Autodesk Fusion 360 part; units mm, degrees
(part 5 of 7)
ref_plane "WorkPlane1" through (-328.5, 0, 0) normal (1, 0, 0) x (0, 1, 0) in component "rear right rail mount 2-1 M6 cap screw"
sketch "New stock profile (83)" plane through (-328.5, 0, 0) normal (1, 0, 0) x (0, 0, -1) in component "rear right rail mount 2-1 M6 cap screw"
  circle A0 centre (-84.1, -195.15) radius 3
extrude "New 1''''''''''''''''''''''''''''''''''''''''''''''''''''''''''''''''''''''''''''''''''" add sketch "New stock profile (83)" along normal blind 40 separate body makes body 209 in component "rear right rail mount 2-1 M6 cap screw"
ref_plane "WorkPlane2" through (-288.5, 0, 0) normal (1, 0, 0) x (0, 1, 0) in component "rear right rail mount 2-1 M6 cap screw"
sketch "Join stock profile (29)" plane through (-288.5, 0, 0) normal (1, 0, 0) x (0, 0, -1) in component "rear right rail mount 2-1 M6 cap screw"
  circle A0 centre (-84.1, -195.15) radius 5
extrude "Join 2''''''''''''''''''''''''''''" add sketch "Join stock profile (29)" along normal blind 6 bodies 209 in component "rear right rail mount 2-1 M6 cap screw"
ref_plane "WorkPlane3" through (-282.49, 0, 0) normal (1, 0, 0) x (0, 1, 0) in component "rear right rail mount 2-1 M6 cap screw"
sketch "Cut stock profile (53)" plane through (-282.49, 0, 0) normal (1, 0, 0) x (0, 0, -1) in component "rear right rail mount 2-1 M6 cap screw"
  line L0 (-84.1, -198.0368) -> (-86.6, -196.5934)
  line L1 (-86.6, -196.5934) -> (-86.6, -193.7066)
  line L2 (-86.6, -193.7066) -> (-84.1, -192.2632)
  line L3 (-84.1, -192.2632) -> (-81.6, -193.7066)
  line L4 (-81.6, -193.7066) -> (-81.6, -196.5934)
  line L5 (-81.6, -196.5934) -> (-84.1, -198.0368)
extrude "Cut 3''''''''''''''''''''''''''''''''''''" cut sketch "Cut stock profile (53)" against normal blind 3.01 bodies 209 in component "rear right rail mount 2-1 M6 cap screw"
ref_plane "WorkPlane1" through (-330.6, 0, 0) normal (1, 0, 0) x (0, 1, 0) in component "rear right rail mount 2-2 weld boss"
sketch "New stock profile (84)" plane through (-330.6, 0, 0) normal (1, 0, 0) x (0, 0, -1) in component "rear right rail mount 2-2 weld boss"
  circle A0 centre (-105.1, -195.15) radius 6.5
  circle A1 centre (-105.1, -195.15) radius 2.5
extrude "New 1'''''''''''''''''''''''''''''''''''''''''''''''''''''''''''''''''''''''''''''''''''" add sketch "New stock profile (84)" along normal blind 16 separate body makes body 210 in component "rear right rail mount 2-2 weld boss"
ref_plane "WorkPlane1" through (-328.5, 0, 0) normal (1, 0, 0) x (0, 1, 0) in component "rear right rail mount 2-2 M6 cap screw"
sketch "New stock profile (85)" plane through (-328.5, 0, 0) normal (1, 0, 0) x (0, 0, -1) in component "rear right rail mount 2-2 M6 cap screw"
  circle A0 centre (-105.1, -195.15) radius 3
extrude "New 1''''''''''''''''''''''''''''''''''''''''''''''''''''''''''''''''''''''''''''''''''''" add sketch "New stock profile (85)" along normal blind 40 separate body makes body 211 in component "rear right rail mount 2-2 M6 cap screw"
ref_plane "WorkPlane2" through (-288.5, 0, 0) normal (1, 0, 0) x (0, 1, 0) in component "rear right rail mount 2-2 M6 cap screw"
sketch "Join stock profile (30)" plane through (-288.5, 0, 0) normal (1, 0, 0) x (0, 0, -1) in component "rear right rail mount 2-2 M6 cap screw"
  circle A0 centre (-105.1, -195.15) radius 5
extrude "Join 2'''''''''''''''''''''''''''''" add sketch "Join stock profile (30)" along normal blind 6 bodies 211 in component "rear right rail mount 2-2 M6 cap screw"
ref_plane "WorkPlane3" through (-282.49, 0, 0) normal (1, 0, 0) x (0, 1, 0) in component "rear right rail mount 2-2 M6 cap screw"
sketch "Cut stock profile (54)" plane through (-282.49, 0, 0) normal (1, 0, 0) x (0, 0, -1) in component "rear right rail mount 2-2 M6 cap screw"
  line L0 (-105.1, -198.0368) -> (-107.6, -196.5934)
  line L1 (-107.6, -196.5934) -> (-107.6, -193.7066)
  line L2 (-107.6, -193.7066) -> (-105.1, -192.2632)
  line L3 (-105.1, -192.2632) -> (-102.6, -193.7066)
  line L4 (-102.6, -193.7066) -> (-102.6, -196.5934)
  line L5 (-102.6, -196.5934) -> (-105.1, -198.0368)
extrude "Cut 3'''''''''''''''''''''''''''''''''''''" cut sketch "Cut stock profile (54)" against normal blind 3.01 bodies 211 in component "rear right rail mount 2-2 M6 cap screw"
ref_plane "WorkPlane1" through (0, 0, 65.5637) normal (0, 0, 1) x (1, 0, 0) in component "rear right tab 2-1 socket screw"
sketch "New stock profile (86)" plane through (0, 0, 65.5637) normal (0, 0, 1) x (1, 0, 0) in component "rear right tab 2-1 socket screw"
  circle A0 centre (-296.75, -207.85) radius 2.413
extrude "New 1'''''''''''''''''''''''''''''''''''''''''''''''''''''''''''''''''''''''''''''''''''''" add sketch "New stock profile (86)" along normal blind 69.85 separate body makes body 212 in component "rear right tab 2-1 socket screw"
ref_plane "WorkPlane2" through (0, 0, 60.7378) normal (0, 0, 1) x (1, 0, 0) in component "rear right tab 2-1 socket screw"
sketch "Join stock profile (31)" plane through (0, 0, 60.7378) normal (0, 0, 1) x (1, 0, 0) in component "rear right tab 2-1 socket screw"
  circle A0 centre (-296.75, -207.85) radius 3.9624
extrude "Join 2''''''''''''''''''''''''''''''" add sketch "Join stock profile (31)" along normal blind 4.826 bodies 212 in component "rear right tab 2-1 socket screw"
ref_plane "WorkPlane3" through (0, 0, 60.7278) normal (0, 0, 1) x (1, 0, 0) in component "rear right tab 2-1 socket screw"
sketch "Cut stock profile (55)" plane through (0, 0, 60.7278) normal (0, 0, 1) x (1, 0, 0) in component "rear right tab 2-1 socket screw"
  line L0 (-294.4586, -207.85) -> (-295.6043, -205.8656)
  line L1 (-295.6043, -205.8656) -> (-297.8957, -205.8656)
  line L2 (-297.8957, -205.8656) -> (-299.0414, -207.85)
  line L3 (-299.0414, -207.85) -> (-297.8957, -209.8344)
  line L4 (-297.8957, -209.8344) -> (-295.6043, -209.8344)
  line L5 (-295.6043, -209.8344) -> (-294.4586, -207.85)
extrude "Cut 3''''''''''''''''''''''''''''''''''''''" cut sketch "Cut stock profile (55)" along normal blind 2.296 bodies 212 in component "rear right tab 2-1 socket screw"
ref_plane "WorkPlane1" through (0, 0, 124.3125) normal (0, 0, 1) x (1, 0, 0) in component "rear right tab 2-1 locknut"
sketch "New stock profile (87)" plane through (0, 0, 124.3125) normal (0, 0, 1) x (1, 0, 0) in component "rear right tab 2-1 locknut"
  line L0 (-291.2361, -207.85) -> (-293.993, -203.0748)
  line L1 (-293.993, -203.0748) -> (-299.507, -203.0748)
  line L2 (-299.507, -203.0748) -> (-302.2639, -207.85)
  line L3 (-302.2639, -207.85) -> (-299.507, -212.6252)
  line L4 (-299.507, -212.6252) -> (-293.993, -212.6252)
  line L5 (-293.993, -212.6252) -> (-291.2361, -207.85)
  circle A0 centre (-296.75, -207.85) radius 2.43
extrude "New 1''''''''''''''''''''''''''''''''''''''''''''''''''''''''''''''''''''''''''''''''''''''" add sketch "New stock profile (87)" along normal blind 6.3246 separate body makes body 213 in component "rear right tab 2-1 locknut"
ref_plane "WorkPlane1" through (0, 0, 65.5637) normal (0, 0, 1) x (1, 0, 0) in component "rear right tab 2-2 socket screw"
sketch "New stock profile (88)" plane through (0, 0, 65.5637) normal (0, 0, 1) x (1, 0, 0) in component "rear right tab 2-2 socket screw"
  circle A0 centre (-296.75, -182.45) radius 2.413
extrude "New 1'''''''''''''''''''''''''''''''''''''''''''''''''''''''''''''''''''''''''''''''''''''''" add sketch "New stock profile (88)" along normal blind 69.85 separate body makes body 214 in component "rear right tab 2-2 socket screw"
ref_plane "WorkPlane2" through (0, 0, 60.7378) normal (0, 0, 1) x (1, 0, 0) in component "rear right tab 2-2 socket screw"
sketch "Join stock profile (32)" plane through (0, 0, 60.7378) normal (0, 0, 1) x (1, 0, 0) in component "rear right tab 2-2 socket screw"
  circle A0 centre (-296.75, -182.45) radius 3.9624
extrude "Join 2'''''''''''''''''''''''''''''''" add sketch "Join stock profile (32)" along normal blind 4.826 bodies 214 in component "rear right tab 2-2 socket screw"
ref_plane "WorkPlane3" through (0, 0, 60.7278) normal (0, 0, 1) x (1, 0, 0) in component "rear right tab 2-2 socket screw"
sketch "Cut stock profile (56)" plane through (0, 0, 60.7278) normal (0, 0, 1) x (1, 0, 0) in component "rear right tab 2-2 socket screw"
  line L0 (-294.4586, -182.45) -> (-295.6043, -180.4656)
  line L1 (-295.6043, -180.4656) -> (-297.8957, -180.4656)
  line L2 (-297.8957, -180.4656) -> (-299.0414, -182.45)
  line L3 (-299.0414, -182.45) -> (-297.8957, -184.4344)
  line L4 (-297.8957, -184.4344) -> (-295.6043, -184.4344)
  line L5 (-295.6043, -184.4344) -> (-294.4586, -182.45)
extrude "Cut 3'''''''''''''''''''''''''''''''''''''''" cut sketch "Cut stock profile (56)" along normal blind 2.296 bodies 214 in component "rear right tab 2-2 socket screw"
ref_plane "WorkPlane1" through (0, 0, 124.3125) normal (0, 0, 1) x (1, 0, 0) in component "rear right tab 2-2 locknut"
sketch "New stock profile (89)" plane through (0, 0, 124.3125) normal (0, 0, 1) x (1, 0, 0) in component "rear right tab 2-2 locknut"
  line L0 (-291.2361, -182.45) -> (-293.993, -177.6748)
  line L1 (-293.993, -177.6748) -> (-299.507, -177.6748)
  line L2 (-299.507, -177.6748) -> (-302.2639, -182.45)
  line L3 (-302.2639, -182.45) -> (-299.507, -187.2252)
  line L4 (-299.507, -187.2252) -> (-293.993, -187.2252)
  line L5 (-293.993, -187.2252) -> (-291.2361, -182.45)
  circle A0 centre (-296.75, -182.45) radius 2.43
extrude "New 1''''''''''''''''''''''''''''''''''''''''''''''''''''''''''''''''''''''''''''''''''''''''" add sketch "New stock profile (89)" along normal blind 6.3246 separate body makes body 215 in component "rear right tab 2-2 locknut"
ref_plane "WorkPlane1" through (0, 0, 3.1) normal (0, 0, 1) x (1, 0, 0) in component "front left public drive housing"
sketch "New stock profile (90)" plane through (0, 0, 3.1) normal (0, 0, 1) x (1, 0, 0) in component "front left public drive housing"
  circle A0 centre (-3, -3) radius 30
  circle A1 centre (-3, -3) radius 20
extrude "New 1'''''''''''''''''''''''''''''''''''''''''''''''''''''''''''''''''''''''''''''''''''''''''" add sketch "New stock profile (90)" along normal blind 48 separate body makes body 216 in component "front left public drive housing"
ref_plane "WorkPlane2" through (0, 0, -1.9) normal (0, 0, 1) x (1, 0, 0) in component "front left public drive housing"
sketch "Join stock profile (33)" plane through (0, 0, -1.9) normal (0, 0, 1) x (1, 0, 0) in component "front left public drive housing"
  line L0 (-29, -29) -> (-15, -29)
  line L1 (-15, -29) -> (-15, -15)
  line L2 (-15, -15) -> (-29, -15)
  line L3 (-29, -15) -> (-29, -29)
extrude "Join 2''''''''''''''''''''''''''''''''" add sketch "Join stock profile (33)" along normal blind 53 bodies 216 in component "front left public drive housing"
ref_plane "WorkPlane3" through (0, 0, -4.4362) normal (0, 0, 1) x (1, 0, 0) in component "front left public drive housing"
sketch "Join stock profile (1)" plane through (0, 0, -4.4362) normal (0, 0, 1) x (1, 0, 0) in component "front left public drive housing"
  line L0 (-29, -28) -> (-22, -28)
  line L1 (-22, -28) -> (-22, 33)
  line L2 (-22, 33) -> (-29, 33)
  line L3 (-29, 33) -> (-29, -28)
extrude "Join 3" add sketch "Join stock profile (1)" along normal blind 4.2863 bodies 216 in component "front left public drive housing"
ref_plane "WorkPlane4" through (0, 0, -4.4362) normal (0, 0, 1) x (1, 0, 0) in component "front left public drive housing"
sketch "Join stock profile (2) (2)" plane through (0, 0, -4.4362) normal (0, 0, 1) x (1, 0, 0) in component "front left public drive housing"
  line L0 (-90.7, 23) -> (-25, 23)
  line L1 (-25, 23) -> (-25, 34)
  line L2 (-25, 34) -> (-90.7, 34)
  line L3 (-90.7, 34) -> (-90.7, 23)
extrude "Join 4" add sketch "Join stock profile (2) (2)" along normal blind 4.2863 bodies 216 in component "front left public drive housing"
ref_plane "WorkPlane5" through (0, 0, -4.4362) normal (0, 0, 1) x (1, 0, 0) in component "front left public drive housing"
sketch "Join stock profile (3) (2)" plane through (0, 0, -4.4362) normal (0, 0, 1) x (1, 0, 0) in component "front left public drive housing"
  line L0 (-28, -29) -> (33, -29)
  line L1 (33, -29) -> (33, -22)
  line L2 (33, -22) -> (-28, -22)
  line L3 (-28, -22) -> (-28, -29)
extrude "Join 5" add sketch "Join stock profile (3) (2)" along normal blind 4.2863 bodies 216 in component "front left public drive housing"
ref_plane "WorkPlane6" through (0, 0, -4.4362) normal (0, 0, 1) x (1, 0, 0) in component "front left public drive housing"
sketch "Join stock profile (4) (2)" plane through (0, 0, -4.4362) normal (0, 0, 1) x (1, 0, 0) in component "front left public drive housing"
  line L0 (23, -90.7) -> (34, -90.7)
  line L1 (34, -90.7) -> (34, -25)
  line L2 (34, -25) -> (23, -25)
  line L3 (23, -25) -> (23, -90.7)
extrude "Join 6" add sketch "Join stock profile (4) (2)" along normal blind 4.2863 bodies 216 in component "front left public drive housing"
ref_plane "WorkPlane7" through (0, 0, -4.4463) normal (0, 0, 1) x (1, 0, 0) in component "front left public drive housing"
sketch "Cut stock profile (57)" plane through (0, 0, -4.4463) normal (0, 0, 1) x (1, 0, 0) in component "front left public drive housing"
  circle A0 centre (-60.15, 28.75) radius 2.5
extrude "Cut 7'''''" cut sketch "Cut stock profile (57)" along normal blind 4.3063 bodies 216 in component "front left public drive housing"
extrude "Extrude4''" [no effect] in component "front left tab 1-1 socket screw"
ref_plane "WorkPlane8" through (0, 0, -4.4463) normal (0, 0, 1) x (1, 0, 0) in component "front left public drive housing"
sketch "Cut stock profile (1) (14)" plane through (0, 0, -4.4463) normal (0, 0, 1) x (1, 0, 0) in component "front left public drive housing"
  circle A0 centre (-85.55, 28.75) radius 2.5
extrude "Cut 8" cut sketch "Cut stock profile (1) (14)" along normal blind 4.3063 bodies 216 in component "front left public drive housing"
extrude "Extrude4'''" [no effect] in component "front left tab 1-2 socket screw"
ref_plane "WorkPlane9" through (0, 0, -4.4463) normal (0, 0, 1) x (1, 0, 0) in component "front left public drive housing"
sketch "Cut stock profile (2) (14)" plane through (0, 0, -4.4463) normal (0, 0, 1) x (1, 0, 0) in component "front left public drive housing"
  circle A0 centre (28.75, -60.15) radius 2.5
extrude "Cut 9" cut sketch "Cut stock profile (2) (14)" along normal blind 4.3063 bodies 216 in component "front left public drive housing"
extrude "Extrude4''''" [no effect] in component "front left tab 2-1 socket screw"
ref_plane "WorkPlane10" through (0, 0, -4.4463) normal (0, 0, 1) x (1, 0, 0) in component "front left public drive housing"
sketch "Cut stock profile (3) (12)" plane through (0, 0, -4.4463) normal (0, 0, 1) x (1, 0, 0) in component "front left public drive housing"
  circle A0 centre (28.75, -85.55) radius 2.5
extrude "Cut 10" cut sketch "Cut stock profile (3) (12)" along normal blind 4.3063 bodies 216 in component "front left public drive housing"
extrude "Extrude4'''''" [no effect] in component "front left tab 2-2 socket screw"
ref_plane "WorkPlane11" through (0, 0, 50.65) normal (0, 0, 1) x (1, 0, 0) in component "front left public drive housing"
sketch "Join stock profile (5) (2)" plane through (0, 0, 50.65) normal (0, 0, 1) x (1, 0, 0) in component "front left public drive housing"
  line L0 (-29, -28) -> (-22, -28)
  line L1 (-22, -28) -> (-22, 33)
  line L2 (-22, 33) -> (-29, 33)
  line L3 (-29, 33) -> (-29, -28)
extrude "Join 11" add sketch "Join stock profile (5) (2)" along normal blind 3.6625 bodies 216 in component "front left public drive housing"
ref_plane "WorkPlane12" through (0, 0, 50.65) normal (0, 0, 1) x (1, 0, 0) in component "front left public drive housing"
sketch "Join stock profile (6) (2)" plane through (0, 0, 50.65) normal (0, 0, 1) x (1, 0, 0) in component "front left public drive housing"
  line L0 (-90.7, 23) -> (-25, 23)
  line L1 (-25, 23) -> (-25, 34)
  line L2 (-25, 34) -> (-90.7, 34)
  line L3 (-90.7, 34) -> (-90.7, 23)
extrude "Join 12" add sketch "Join stock profile (6) (2)" along normal blind 3.6625 bodies 216 in component "front left public drive housing"
ref_plane "WorkPlane13" through (0, 0, 50.65) normal (0, 0, 1) x (1, 0, 0) in component "front left public drive housing"
sketch "Join stock profile (7) (2)" plane through (0, 0, 50.65) normal (0, 0, 1) x (1, 0, 0) in component "front left public drive housing"
  line L0 (-28, -29) -> (33, -29)
  line L1 (33, -29) -> (33, -22)
  line L2 (33, -22) -> (-28, -22)
  line L3 (-28, -22) -> (-28, -29)
extrude "Join 13" add sketch "Join stock profile (7) (2)" along normal blind 3.6625 bodies 216 in component "front left public drive housing"
ref_plane "WorkPlane14" through (0, 0, 50.65) normal (0, 0, 1) x (1, 0, 0) in component "front left public drive housing"
sketch "Join stock profile (8) (2)" plane through (0, 0, 50.65) normal (0, 0, 1) x (1, 0, 0) in component "front left public drive housing"
  line L0 (23, -90.7) -> (34, -90.7)
  line L1 (34, -90.7) -> (34, -25)
  line L2 (34, -25) -> (23, -25)
  line L3 (23, -25) -> (23, -90.7)
extrude "Join 14" add sketch "Join stock profile (8) (2)" along normal blind 3.6625 bodies 216 in component "front left public drive housing"
ref_plane "WorkPlane15" through (0, 0, 50.64) normal (0, 0, 1) x (1, 0, 0) in component "front left public drive housing"
sketch "Cut stock profile (4) (12)" plane through (0, 0, 50.64) normal (0, 0, 1) x (1, 0, 0) in component "front left public drive housing"
  circle A0 centre (-60.15, 28.75) radius 2.5
extrude "Cut 15" cut sketch "Cut stock profile (4) (12)" along normal blind 3.6825 bodies 216 in component "front left public drive housing"
extrude "Extrude5''" [no effect] in component "front left tab 1-1 socket screw"
extrude "Extrude2'''" [no effect] in component "front left tab 1-1 locknut"
ref_plane "WorkPlane16" through (0, 0, 50.64) normal (0, 0, 1) x (1, 0, 0) in component "front left public drive housing"
sketch "Cut stock profile (5) (10)" plane through (0, 0, 50.64) normal (0, 0, 1) x (1, 0, 0) in component "front left public drive housing"
  circle A0 centre (-85.55, 28.75) radius 2.5
extrude "Cut 16" cut sketch "Cut stock profile (5) (10)" along normal blind 3.6825 bodies 216 in component "front left public drive housing"
extrude "Extrude5'''" [no effect] in component "front left tab 1-2 socket screw"
extrude "Extrude2''''" [no effect] in component "front left tab 1-2 locknut"
ref_plane "WorkPlane17" through (0, 0, 50.64) normal (0, 0, 1) x (1, 0, 0) in component "front left public drive housing"
sketch "Cut stock profile (6) (2)" plane through (0, 0, 50.64) normal (0, 0, 1) x (1, 0, 0) in component "front left public drive housing"
  circle A0 centre (28.75, -60.15) radius 2.5
extrude "Cut 17" cut sketch "Cut stock profile (6) (2)" along normal blind 3.6825 bodies 216 in component "front left public drive housing"
extrude "Extrude5''''" [no effect] in component "front left tab 2-1 socket screw"
extrude "Extrude2'''''" [no effect] in component "front left tab 2-1 locknut"
ref_plane "WorkPlane18" through (0, 0, 50.64) normal (0, 0, 1) x (1, 0, 0) in component "front left public drive housing"
sketch "Cut stock profile (7) (2)" plane through (0, 0, 50.64) normal (0, 0, 1) x (1, 0, 0) in component "front left public drive housing"
  circle A0 centre (28.75, -85.55) radius 2.5
extrude "Cut 18" cut sketch "Cut stock profile (7) (2)" along normal blind 3.6825 bodies 216 in component "front left public drive housing"
extrude "Extrude5'''''" [no effect] in component "front left tab 2-2 socket screw"
extrude "Extrude2''''''" [no effect] in component "front left tab 2-2 locknut"
ref_plane "WorkPlane1" through (0, 0, 6.1) normal (0, 0, 1) x (1, 0, 0) in component "front left public motor reserve"
sketch "New stock profile (91)" plane through (0, 0, 6.1) normal (0, 0, 1) x (1, 0, 0) in component "front left public motor reserve"
  circle A0 centre (-19, -19) radius 19
extrude "New 1''''''''''''''''''''''''''''''''''''''''''''''''''''''''''''''''''''''''''''''''''''''''''" add sketch "New stock profile (91)" along normal blind 50.36 separate body makes body 217 in component "front left public motor reserve"
ref_plane "WorkPlane1" through (0, 0, 68.1) normal (0, 0, 1) x (1, 0, 0) in component "front left public turning fork"
sketch "New stock profile (92)" plane through (0, 0, 68.1) normal (0, 0, 1) x (1, 0, 0) in component "front left public turning fork"
  circle A0 centre (265, 265) radius 19.95
extrude "New 1'''''''''''''''''''''''''''''''''''''''''''''''''''''''''''''''''''''''''''''''''''''''''''" add sketch "New stock profile (92)" along normal blind 23 separate body makes body 218 in component "front left public turning fork"
ref_plane "WorkPlane2" through (0, 0, 68.1) normal (0, 0, 1) x (1, 0, 0) in component "front left public turning fork"
sketch "Join stock profile (34)" plane through (0, 0, 68.1) normal (0, 0, 1) x (1, 0, 0) in component "front left public turning fork"
  circle A0 centre (265, 265) radius 25.5
extrude "Join 2'''''''''''''''''''''''''''''''''" add sketch "Join stock profile (34)" along normal blind 5 bodies 218 in component "front left public turning fork"
ref_plane "WorkPlane3" through (0, 0, 33.1) normal (0, 0, 1) x (1, 0, 0) in component "front left public turning fork"
sketch "Join stock profile (1) (2)" plane through (0, 0, 33.1) normal (0, 0, 1) x (1, 0, 0) in component "front left public turning fork"
  line L0 (258, 279) -> (272, 279)
  line L1 (272, 279) -> (272, 286)
  line L2 (272, 286) -> (258, 286)
  line L3 (258, 286) -> (258, 279)
extrude "Join 3'" add sketch "Join stock profile (1) (2)" along normal blind 39 bodies 218 in component "front left public turning fork"
ref_plane "WorkPlane4" through (0, 0, 33.1) normal (0, 0, 1) x (1, 0, 0) in component "front left public turning fork"
sketch "Join stock profile (2) (3)" plane through (0, 0, 33.1) normal (0, 0, 1) x (1, 0, 0) in component "front left public turning fork"
  line L0 (258, 244) -> (272, 244)
  line L1 (272, 244) -> (272, 251)
  line L2 (272, 251) -> (258, 251)
  line L3 (258, 251) -> (258, 244)
extrude "Join 4'" add sketch "Join stock profile (2) (3)" along normal blind 39 bodies 218 in component "front left public turning fork"
ref_plane "WorkPlane5" through (0, 287, 0) normal (0, 1, 0) x (0, 0, 1) in component "front left public turning fork"
sketch "Cut stock profile (58)" plane through (0, 287, 0) normal (0, 1, 0) x (1, 0, 0) in component "front left public turning fork"
  circle A0 centre (265, -38.1) radius 5
ref_plane "WorkPlane1" through (0, 286, 0) normal (0, 1, 0) x (0, 0, 1) in component "front left public wheel axle"
sketch "New stock profile (93)" plane through (0, 286, 0) normal (0, 1, 0) x (1, 0, 0) in component "front left public wheel axle"
  circle A0 centre (265, -38.1) radius 5
extrude "New 1''''''''''''''''''''''''''''''''''''''''''''''''''''''''''''''''''''''''''''''''''''''''''''" add sketch "New stock profile (93)" against normal blind 42 separate body makes body 219 in component "front left public wheel axle"
ref_plane "WorkPlane1" through (0, 0, 23) normal (0, 0, 1) x (1, 0, 0) in component "front left public wheel"
sketch "New stock profile (94)" plane through (0, 0, 23) normal (0, 0, 1) x (1, 0, 0) in component "front left public wheel"
  circle A0 centre (3, 0) radius 38.1
  circle A1 centre (3, 0) radius 5
extrude "New 1'''''''''''''''''''''''''''''''''''''''''''''''''''''''''''''''''''''''''''''''''''''''''''''" add sketch "New stock profile (94)" against normal blind 26 separate body makes body 220 in component "front left public wheel"
ref_plane "WorkPlane1" through (0, 0, 3.1) normal (0, 0, 1) x (1, 0, 0) in component "front right public drive housing"
sketch "New stock profile (95)" plane through (0, 0, 3.1) normal (0, 0, 1) x (1, 0, 0) in component "front right public drive housing"
  circle A0 centre (-3, 3) radius 30
  circle A1 centre (-3, 3) radius 20
extrude "New 1''''''''''''''''''''''''''''''''''''''''''''''''''''''''''''''''''''''''''''''''''''''''''''''" add sketch "New stock profile (95)" along normal blind 48 separate body makes body 221 in component "front right public drive housing"
ref_plane "WorkPlane2" through (0, 0, -1.9) normal (0, 0, 1) x (1, 0, 0) in component "front right public drive housing"
sketch "Join stock profile (35)" plane through (0, 0, -1.9) normal (0, 0, 1) x (1, 0, 0) in component "front right public drive housing"
  line L0 (-29, 15) -> (-15, 15)
  line L1 (-15, 15) -> (-15, 29)
  line L2 (-15, 29) -> (-29, 29)
  line L3 (-29, 29) -> (-29, 15)
extrude "Join 2''''''''''''''''''''''''''''''''''" add sketch "Join stock profile (35)" along normal blind 53 bodies 221 in component "front right public drive housing"
ref_plane "WorkPlane3" through (0, 0, -4.4362) normal (0, 0, 1) x (1, 0, 0) in component "front right public drive housing"
sketch "Join stock profile (1) (3)" plane through (0, 0, -4.4362) normal (0, 0, 1) x (1, 0, 0) in component "front right public drive housing"
  line L0 (-28, 22) -> (33, 22)
  line L1 (33, 22) -> (33, 29)
  line L2 (33, 29) -> (-28, 29)
  line L3 (-28, 29) -> (-28, 22)
extrude "Join 3''" add sketch "Join stock profile (1) (3)" along normal blind 4.2863 bodies 221 in component "front right public drive housing"
ref_plane "WorkPlane4" through (0, 0, -4.4362) normal (0, 0, 1) x (1, 0, 0) in component "front right public drive housing"
sketch "Join stock profile (2) (4)" plane through (0, 0, -4.4362) normal (0, 0, 1) x (1, 0, 0) in component "front right public drive housing"
  line L0 (23, 25) -> (34, 25)
  line L1 (34, 25) -> (34, 90.7)
  line L2 (34, 90.7) -> (23, 90.7)
  line L3 (23, 90.7) -> (23, 25)
extrude "Join 4''" add sketch "Join stock profile (2) (4)" along normal blind 4.2863 bodies 221 in component "front right public drive housing"
ref_plane "WorkPlane5" through (0, 0, -4.4362) normal (0, 0, 1) x (1, 0, 0) in component "front right public drive housing"
sketch "Join stock profile (3) (3)" plane through (0, 0, -4.4362) normal (0, 0, 1) x (1, 0, 0) in component "front right public drive housing"
  line L0 (-29, -33) -> (-22, -33)
  line L1 (-22, -33) -> (-22, 28)
  line L2 (-22, 28) -> (-29, 28)
  line L3 (-29, 28) -> (-29, -33)
extrude "Join 5'" add sketch "Join stock profile (3) (3)" along normal blind 4.2863 bodies 221 in component "front right public drive housing"
ref_plane "WorkPlane6" through (0, 0, -4.4362) normal (0, 0, 1) x (1, 0, 0) in component "front right public drive housing"
sketch "Join stock profile (4) (3)" plane through (0, 0, -4.4362) normal (0, 0, 1) x (1, 0, 0) in component "front right public drive housing"
  line L0 (-90.7, -34) -> (-25, -34)
  line L1 (-25, -34) -> (-25, -23)
  line L2 (-25, -23) -> (-90.7, -23)
  line L3 (-90.7, -23) -> (-90.7, -34)
extrude "Join 6'" add sketch "Join stock profile (4) (3)" along normal blind 4.2863 bodies 221 in component "front right public drive housing"
ref_plane "WorkPlane7" through (0, 0, -4.4463) normal (0, 0, 1) x (1, 0, 0) in component "front right public drive housing"
sketch "Cut stock profile (59)" plane through (0, 0, -4.4463) normal (0, 0, 1) x (1, 0, 0) in component "front right public drive housing"
  circle A0 centre (28.75, 60.15) radius 2.5
extrude "Cut 7''''''" cut sketch "Cut stock profile (59)" along normal blind 4.3063 bodies 221 in component "front right public drive housing"
extrude "Extrude4''''''" [no effect] in component "front right tab 1-1 socket screw"
ref_plane "WorkPlane8" through (0, 0, -4.4463) normal (0, 0, 1) x (1, 0, 0) in component "front right public drive housing"
sketch "Cut stock profile (1) (15)" plane through (0, 0, -4.4463) normal (0, 0, 1) x (1, 0, 0) in component "front right public drive housing"
  circle A0 centre (28.75, 85.55) radius 2.5
extrude "Cut 8'" cut sketch "Cut stock profile (1) (15)" along normal blind 4.3063 bodies 221 in component "front right public drive housing"
extrude "Extrude4'''''''" [no effect] in component "front right tab 1-2 socket screw"
ref_plane "WorkPlane9" through (0, 0, -4.4463) normal (0, 0, 1) x (1, 0, 0) in component "front right public drive housing"
sketch "Cut stock profile (2) (15)" plane through (0, 0, -4.4463) normal (0, 0, 1) x (1, 0, 0) in component "front right public drive housing"
  circle A0 centre (-60.15, -28.75) radius 2.5
extrude "Cut 9'" cut sketch "Cut stock profile (2) (15)" along normal blind 4.3063 bodies 221 in component "front right public drive housing"
extrude "Extrude4''''''''" [no effect] in component "front right tab 2-1 socket screw"
ref_plane "WorkPlane10" through (0, 0, -4.4463) normal (0, 0, 1) x (1, 0, 0) in component "front right public drive housing"
sketch "Cut stock profile (3) (13)" plane through (0, 0, -4.4463) normal (0, 0, 1) x (1, 0, 0) in component "front right public drive housing"
  circle A0 centre (-85.55, -28.75) radius 2.5
extrude "Cut 10'" cut sketch "Cut stock profile (3) (13)" along normal blind 4.3063 bodies 221 in component "front right public drive housing"
extrude "Extrude4'''''''''" [no effect] in component "front right tab 2-2 socket screw"
ref_plane "WorkPlane11" through (0, 0, 50.65) normal (0, 0, 1) x (1, 0, 0) in component "front right public drive housing"
sketch "Join stock profile (5) (3)" plane through (0, 0, 50.65) normal (0, 0, 1) x (1, 0, 0) in component "front right public drive housing"
  line L0 (-28, 22) -> (33, 22)
  line L1 (33, 22) -> (33, 29)
  line L2 (33, 29) -> (-28, 29)
  line L3 (-28, 29) -> (-28, 22)
extrude "Join 11'" add sketch "Join stock profile (5) (3)" along normal blind 3.6625 bodies 221 in component "front right public drive housing"
ref_plane "WorkPlane12" through (0, 0, 50.65) normal (0, 0, 1) x (1, 0, 0) in component "front right public drive housing"
sketch "Join stock profile (6) (3)" plane through (0, 0, 50.65) normal (0, 0, 1) x (1, 0, 0) in component "front right public drive housing"
  line L0 (23, 25) -> (34, 25)
  line L1 (34, 25) -> (34, 90.7)
  line L2 (34, 90.7) -> (23, 90.7)
  line L3 (23, 90.7) -> (23, 25)
extrude "Join 12'" add sketch "Join stock profile (6) (3)" along normal blind 3.6625 bodies 221 in component "front right public drive housing"
ref_plane "WorkPlane13" through (0, 0, 50.65) normal (0, 0, 1) x (1, 0, 0) in component "front right public drive housing"
sketch "Join stock profile (7) (3)" plane through (0, 0, 50.65) normal (0, 0, 1) x (1, 0, 0) in component "front right public drive housing"
  line L0 (-29, -33) -> (-22, -33)
  line L1 (-22, -33) -> (-22, 28)
  line L2 (-22, 28) -> (-29, 28)
  line L3 (-29, 28) -> (-29, -33)
extrude "Join 13'" add sketch "Join stock profile (7) (3)" along normal blind 3.6625 bodies 221 in component "front right public drive housing"
ref_plane "WorkPlane14" through (0, 0, 50.65) normal (0, 0, 1) x (1, 0, 0) in component "front right public drive housing"
sketch "Join stock profile (8) (3)" plane through (0, 0, 50.65) normal (0, 0, 1) x (1, 0, 0) in component "front right public drive housing"
  line L0 (-90.7, -34) -> (-25, -34)
  line L1 (-25, -34) -> (-25, -23)
  line L2 (-25, -23) -> (-90.7, -23)
  line L3 (-90.7, -23) -> (-90.7, -34)
extrude "Join 14'" add sketch "Join stock profile (8) (3)" along normal blind 3.6625 bodies 221 in component "front right public drive housing"
ref_plane "WorkPlane15" through (0, 0, 50.64) normal (0, 0, 1) x (1, 0, 0) in component "front right public drive housing"
sketch "Cut stock profile (4) (13)" plane through (0, 0, 50.64) normal (0, 0, 1) x (1, 0, 0) in component "front right public drive housing"
  circle A0 centre (28.75, 60.15) radius 2.5
extrude "Cut 15'" cut sketch "Cut stock profile (4) (13)" along normal blind 3.6825 bodies 221 in component "front right public drive housing"
extrude "Extrude5''''''" [no effect] in component "front right tab 1-1 socket screw"
extrude "Extrude2'''''''" [no effect] in component "front right tab 1-1 locknut"
ref_plane "WorkPlane16" through (0, 0, 50.64) normal (0, 0, 1) x (1, 0, 0) in component "front right public drive housing"
sketch "Cut stock profile (5) (11)" plane through (0, 0, 50.64) normal (0, 0, 1) x (1, 0, 0) in component "front right public drive housing"
  circle A0 centre (28.75, 85.55) radius 2.5
extrude "Cut 16'" cut sketch "Cut stock profile (5) (11)" along normal blind 3.6825 bodies 221 in component "front right public drive housing"
extrude "Extrude5'''''''" [no effect] in component "front right tab 1-2 socket screw"
extrude "Extrude2''''''''" [no effect] in component "front right tab 1-2 locknut"
ref_plane "WorkPlane17" through (0, 0, 50.64) normal (0, 0, 1) x (1, 0, 0) in component "front right public drive housing"
sketch "Cut stock profile (6) (3)" plane through (0, 0, 50.64) normal (0, 0, 1) x (1, 0, 0) in component "front right public drive housing"
  circle A0 centre (-60.15, -28.75) radius 2.5
extrude "Cut 17'" cut sketch "Cut stock profile (6) (3)" along normal blind 3.6825 bodies 221 in component "front right public drive housing"
extrude "Extrude5''''''''" [no effect] in component "front right tab 2-1 socket screw"
extrude "Extrude2'''''''''" [no effect] in component "front right tab 2-1 locknut"
ref_plane "WorkPlane18" through (0, 0, 50.64) normal (0, 0, 1) x (1, 0, 0) in component "front right public drive housing"
sketch "Cut stock profile (7) (3)" plane through (0, 0, 50.64) normal (0, 0, 1) x (1, 0, 0) in component "front right public drive housing"
  circle A0 centre (-85.55, -28.75) radius 2.5
extrude "Cut 18'" cut sketch "Cut stock profile (7) (3)" along normal blind 3.6825 bodies 221 in component "front right public drive housing"
extrude "Extrude5'''''''''" [no effect] in component "front right tab 2-2 socket screw"
extrude "Extrude2''''''''''" [no effect] in component "front right tab 2-2 locknut"
ref_plane "WorkPlane1" through (0, 0, 6.1) normal (0, 0, 1) x (1, 0, 0) in component "front right public motor reserve"
sketch "New stock profile (96)" plane through (0, 0, 6.1) normal (0, 0, 1) x (1, 0, 0) in component "front right public motor reserve"
  circle A0 centre (-19, 19) radius 19
extrude "New 1'''''''''''''''''''''''''''''''''''''''''''''''''''''''''''''''''''''''''''''''''''''''''''''''" add sketch "New stock profile (96)" along normal blind 50.36 separate body makes body 222 in component "front right public motor reserve"
ref_plane "WorkPlane1" through (0, 0, 68.1) normal (0, 0, 1) x (1, 0, 0) in component "front right public turning fork"
sketch "New stock profile (97)" plane through (0, 0, 68.1) normal (0, 0, 1) x (1, 0, 0) in component "front right public turning fork"
  circle A0 centre (265, -265) radius 19.95
extrude "New 1''''''''''''''''''''''''''''''''''''''''''''''''''''''''''''''''''''''''''''''''''''''''''''''''" add sketch "New stock profile (97)" along normal blind 23 separate body makes body 223 in component "front right public turning fork"
ref_plane "WorkPlane2" through (0, 0, 68.1) normal (0, 0, 1) x (1, 0, 0) in component "front right public turning fork"
sketch "Join stock profile (36)" plane through (0, 0, 68.1) normal (0, 0, 1) x (1, 0, 0) in component "front right public turning fork"
  circle A0 centre (265, -265) radius 25.5
extrude "Join 2'''''''''''''''''''''''''''''''''''" add sketch "Join stock profile (36)" along normal blind 5 bodies 223 in component "front right public turning fork"
ref_plane "WorkPlane3" through (0, 0, 33.1) normal (0, 0, 1) x (1, 0, 0) in component "front right public turning fork"
sketch "Join stock profile (1) (4)" plane through (0, 0, 33.1) normal (0, 0, 1) x (1, 0, 0) in component "front right public turning fork"
  line L0 (279, -272) -> (286, -272)
  line L1 (286, -272) -> (286, -258)
  line L2 (286, -258) -> (279, -258)
  line L3 (279, -258) -> (279, -272)
extrude "Join 3'''" add sketch "Join stock profile (1) (4)" along normal blind 39 bodies 223 in component "front right public turning fork"
ref_plane "WorkPlane4" through (0, 0, 33.1) normal (0, 0, 1) x (1, 0, 0) in component "front right public turning fork"
sketch "Join stock profile (2) (5)" plane through (0, 0, 33.1) normal (0, 0, 1) x (1, 0, 0) in component "front right public turning fork"
  line L0 (244, -272) -> (251, -272)
  line L1 (251, -272) -> (251, -258)
  line L2 (251, -258) -> (244, -258)
  line L3 (244, -258) -> (244, -272)
extrude "Join 4'''" add sketch "Join stock profile (2) (5)" along normal blind 39 bodies 223 in component "front right public turning fork"
ref_plane "WorkPlane5" through (287, 0, 0) normal (1, 0, 0) x (0, 1, 0) in component "front right public turning fork"
sketch "Cut stock profile (60)" plane through (287, 0, 0) normal (1, 0, 0) x (0, 0, -1) in component "front right public turning fork"
  circle A0 centre (-38.1, -265) radius 5
ref_plane "WorkPlane1" through (286, 0, 0) normal (1, 0, 0) x (0, 1, 0) in component "front right public wheel axle"
sketch "New stock profile (98)" plane through (286, 0, 0) normal (1, 0, 0) x (0, 0, -1) in component "front right public wheel axle"
  circle A0 centre (-38.1, -265) radius 5
extrude "New 1'''''''''''''''''''''''''''''''''''''''''''''''''''''''''''''''''''''''''''''''''''''''''''''''''" add sketch "New stock profile (98)" against normal blind 42 separate body makes body 224 in component "front right public wheel axle"
ref_plane "WorkPlane1" through (-10, 0, 0) normal (1, 0, 0) x (0, 1, 0) in component "front right public wheel"
sketch "New stock profile (99)" plane through (-10, 0, 0) normal (1, 0, 0) x (0, 0, -1) in component "front right public wheel"
  circle A0 centre (-16, 0) radius 38.1
  circle A1 centre (-16, 0) radius 5
extrude "New 1''''''''''''''''''''''''''''''''''''''''''''''''''''''''''''''''''''''''''''''''''''''''''''''''''" add sketch "New stock profile (99)" along normal blind 26 separate body makes body 225 in component "front right public wheel"
ref_plane "WorkPlane1" through (0, 0, 3.1) normal (0, 0, 1) x (1, 0, 0) in component "rear left public drive housing"
sketch "New stock profile (100)" plane through (0, 0, 3.1) normal (0, 0, 1) x (1, 0, 0) in component "rear left public drive housing"
  circle A0 centre (3, -3) radius 30
  circle A1 centre (3, -3) radius 20
extrude "New 1'''''''''''''''''''''''''''''''''''''''''''''''''''''''''''''''''''''''''''''''''''''''''''''''''''" add sketch "New stock profile (100)" along normal blind 48 separate body makes body 226 in component "rear left public drive housing"
ref_plane "WorkPlane2" through (0, 0, -1.9) normal (0, 0, 1) x (1, 0, 0) in component "rear left public drive housing"
sketch "Join stock profile (37)" plane through (0, 0, -1.9) normal (0, 0, 1) x (1, 0, 0) in component "rear left public drive housing"
  line L0 (15, -29) -> (29, -29)
  line L1 (29, -29) -> (29, -15)
  line L2 (29, -15) -> (15, -15)
  line L3 (15, -15) -> (15, -29)
extrude "Join 2''''''''''''''''''''''''''''''''''''" add sketch "Join stock profile (37)" along normal blind 53 bodies 226 in component "rear left public drive housing"
ref_plane "WorkPlane3" through (0, 0, -4.4362) normal (0, 0, 1) x (1, 0, 0) in component "rear left public drive housing"
sketch "Join stock profile (1) (5)" plane through (0, 0, -4.4362) normal (0, 0, 1) x (1, 0, 0) in component "rear left public drive housing"
  line L0 (-33, -29) -> (28, -29)
  line L1 (28, -29) -> (28, -22)
  line L2 (28, -22) -> (-33, -22)
  line L3 (-33, -22) -> (-33, -29)
extrude "Join 3''''" add sketch "Join stock profile (1) (5)" along normal blind 4.2863 bodies 226 in component "rear left public drive housing"
ref_plane "WorkPlane4" through (0, 0, -4.4362) normal (0, 0, 1) x (1, 0, 0) in component "rear left public drive housing"
sketch "Join stock profile (2) (6)" plane through (0, 0, -4.4362) normal (0, 0, 1) x (1, 0, 0) in component "rear left public drive housing"
  line L0 (-34, -90.7) -> (-23, -90.7)
  line L1 (-23, -90.7) -> (-23, -25)
  line L2 (-23, -25) -> (-34, -25)
  line L3 (-34, -25) -> (-34, -90.7)
extrude "Join 4''''" add sketch "Join stock profile (2) (6)" along normal blind 4.2863 bodies 226 in component "rear left public drive housing"
ref_plane "WorkPlane5" through (0, 0, -4.4362) normal (0, 0, 1) x (1, 0, 0) in component "rear left public drive housing"
sketch "Join stock profile (3) (4)" plane through (0, 0, -4.4362) normal (0, 0, 1) x (1, 0, 0) in component "rear left public drive housing"
  line L0 (22, -28) -> (29, -28)
  line L1 (29, -28) -> (29, 33)
  line L2 (29, 33) -> (22, 33)
  line L3 (22, 33) -> (22, -28)
extrude "Join 5''" add sketch "Join stock profile (3) (4)" along normal blind 4.2863 bodies 226 in component "rear left public drive housing"
ref_plane "WorkPlane6" through (0, 0, -4.4362) normal (0, 0, 1) x (1, 0, 0) in component "rear left public drive housing"
sketch "Join stock profile (4) (4)" plane through (0, 0, -4.4362) normal (0, 0, 1) x (1, 0, 0) in component "rear left public drive housing"
  line L0 (25, 23) -> (90.7, 23)
  line L1 (90.7, 23) -> (90.7, 34)
  line L2 (90.7, 34) -> (25, 34)
  line L3 (25, 34) -> (25, 23)
extrude "Join 6''" add sketch "Join stock profile (4) (4)" along normal blind 4.2863 bodies 226 in component "rear left public drive housing"
ref_plane "WorkPlane7" through (0, 0, -4.4463) normal (0, 0, 1) x (1, 0, 0) in component "rear left public drive housing"
sketch "Cut stock profile (61)" plane through (0, 0, -4.4463) normal (0, 0, 1) x (1, 0, 0) in component "rear left public drive housing"
  circle A0 centre (-28.75, -60.15) radius 2.5
extrude "Cut 7'''''''" cut sketch "Cut stock profile (61)" along normal blind 4.3063 bodies 226 in component "rear left public drive housing"
extrude "Extrude4''''''''''" [no effect] in component "rear left tab 1-1 socket screw"
ref_plane "WorkPlane8" through (0, 0, -4.4463) normal (0, 0, 1) x (1, 0, 0) in component "rear left public drive housing"
sketch "Cut stock profile (1) (16)" plane through (0, 0, -4.4463) normal (0, 0, 1) x (1, 0, 0) in component "rear left public drive housing"
  circle A0 centre (-28.75, -85.55) radius 2.5
extrude "Cut 8''" cut sketch "Cut stock profile (1) (16)" along normal blind 4.3063 bodies 226 in component "rear left public drive housing"
extrude "Extrude4'''''''''''" [no effect] in component "rear left tab 1-2 socket screw"
ref_plane "WorkPlane9" through (0, 0, -4.4463) normal (0, 0, 1) x (1, 0, 0) in component "rear left public drive housing"
sketch "Cut stock profile (2) (16)" plane through (0, 0, -4.4463) normal (0, 0, 1) x (1, 0, 0) in component "rear left public drive housing"
  circle A0 centre (60.15, 28.75) radius 2.5
extrude "Cut 9''" cut sketch "Cut stock profile (2) (16)" along normal blind 4.3063 bodies 226 in component "rear left public drive housing"
extrude "Extrude4''''''''''''" [no effect] in component "rear left tab 2-1 socket screw"
ref_plane "WorkPlane10" through (0, 0, -4.4463) normal (0, 0, 1) x (1, 0, 0) in component "rear left public drive housing"
sketch "Cut stock profile (3) (14)" plane through (0, 0, -4.4463) normal (0, 0, 1) x (1, 0, 0) in component "rear left public drive housing"
  circle A0 centre (85.55, 28.75) radius 2.5
extrude "Cut 10''" cut sketch "Cut stock profile (3) (14)" along normal blind 4.3063 bodies 226 in component "rear left public drive housing"
extrude "Extrude4'''''''''''''" [no effect] in component "rear left tab 2-2 socket screw"
ref_plane "WorkPlane11" through (0, 0, 50.65) normal (0, 0, 1) x (1, 0, 0) in component "rear left public drive housing"
sketch "Join stock profile (5) (4)" plane through (0, 0, 50.65) normal (0, 0, 1) x (1, 0, 0) in component "rear left public drive housing"
  line L0 (-33, -29) -> (28, -29)
  line L1 (28, -29) -> (28, -22)
  line L2 (28, -22) -> (-33, -22)
  line L3 (-33, -22) -> (-33, -29)
extrude "Join 11''" add sketch "Join stock profile (5) (4)" along normal blind 3.6625 bodies 226 in component "rear left public drive housing"
ref_plane "WorkPlane12" through (0, 0, 50.65) normal (0, 0, 1) x (1, 0, 0) in component "rear left public drive housing"
sketch "Join stock profile (6) (4)" plane through (0, 0, 50.65) normal (0, 0, 1) x (1, 0, 0) in component "rear left public drive housing"
  line L0 (-34, -90.7) -> (-23, -90.7)
  line L1 (-23, -90.7) -> (-23, -25)
  line L2 (-23, -25) -> (-34, -25)
  line L3 (-34, -25) -> (-34, -90.7)
  dimension "d284" = 0
  dimension "d408" = 0
extrude "Join 12''" add sketch "Join stock profile (6) (4)" along normal blind 3.6625 bodies 226 in component "rear left public drive housing"
ref_plane "WorkPlane13" through (0, 0, 50.65) normal (0, 0, 1) x (1, 0, 0) in component "rear left public drive housing"
sketch "Join stock profile (7) (4)" plane through (0, 0, 50.65) normal (0, 0, 1) x (1, 0, 0) in component "rear left public drive housing"
  line L0 (22, -28) -> (29, -28)
  line L1 (29, -28) -> (29, 33)
  line L2 (29, 33) -> (22, 33)
  line L3 (22, 33) -> (22, -28)
extrude "Join 13''" add sketch "Join stock profile (7) (4)" along normal blind 3.6625 bodies 226 in component "rear left public drive housing"
ref_plane "WorkPlane14" through (0, 0, 50.65) normal (0, 0, 1) x (1, 0, 0) in component "rear left public drive housing"
sketch "Join stock profile (8) (4)" plane through (0, 0, 50.65) normal (0, 0, 1) x (1, 0, 0) in component "rear left public drive housing"
  line L0 (25, 23) -> (90.7, 23)
  line L1 (90.7, 23) -> (90.7, 34)
  line L2 (90.7, 34) -> (25, 34)
  line L3 (25, 34) -> (25, 23)
extrude "Join 14''" add sketch "Join stock profile (8) (4)" along normal blind 3.6625 bodies 226 in component "rear left public drive housing"
ref_plane "WorkPlane15" through (0, 0, 50.64) normal (0, 0, 1) x (1, 0, 0) in component "rear left public drive housing"
sketch "Cut stock profile (4) (14)" plane through (0, 0, 50.64) normal (0, 0, 1) x (1, 0, 0) in component "rear left public drive housing"
  circle A0 centre (-28.75, -60.15) radius 2.5
extrude "Cut 15''" cut sketch "Cut stock profile (4) (14)" along normal blind 3.6825 bodies 226 in component "rear left public drive housing"
extrude "Extrude5''''''''''" [no effect] in component "rear left tab 1-1 socket screw"
extrude "Extrude2'''''''''''" [no effect] in component "rear left tab 1-1 locknut"
ref_plane "WorkPlane16" through (0, 0, 50.64) normal (0, 0, 1) x (1, 0, 0) in component "rear left public drive housing"
sketch "Cut stock profile (5) (12)" plane through (0, 0, 50.64) normal (0, 0, 1) x (1, 0, 0) in component "rear left public drive housing"
  circle A0 centre (-28.75, -85.55) radius 2.5
extrude "Cut 16''" cut sketch "Cut stock profile (5) (12)" along normal blind 3.6825 bodies 226 in component "rear left public drive housing"
extrude "Extrude5'''''''''''" [no effect] in component "rear left tab 1-2 socket screw"
extrude "Extrude2''''''''''''" [no effect] in component "rear left tab 1-2 locknut"
ref_plane "WorkPlane17" through (0, 0, 50.64) normal (0, 0, 1) x (1, 0, 0) in component "rear left public drive housing"
sketch "Cut stock profile (6) (4)" plane through (0, 0, 50.64) normal (0, 0, 1) x (1, 0, 0) in component "rear left public drive housing"
  circle A0 centre (60.15, 28.75) radius 2.5
extrude "Cut 17''" cut sketch "Cut stock profile (6) (4)" along normal blind 3.6825 bodies 226 in component "rear left public drive housing"
extrude "Extrude5''''''''''''" [no effect] in component "rear left tab 2-1 socket screw"
extrude "Extrude2'''''''''''''" [no effect] in component "rear left tab 2-1 locknut"
ref_plane "WorkPlane18" through (0, 0, 50.64) normal (0, 0, 1) x (1, 0, 0) in component "rear left public drive housing"
sketch "Cut stock profile (7) (4)" plane through (0, 0, 50.64) normal (0, 0, 1) x (1, 0, 0) in component "rear left public drive housing"
  circle A0 centre (85.55, 28.75) radius 2.5
extrude "Cut 18''" cut sketch "Cut stock profile (7) (4)" along normal blind 3.6825 bodies 226 in component "rear left public drive housing"
extrude "Extrude5'''''''''''''" [no effect] in component "rear left tab 2-2 socket screw"
extrude "Extrude2''''''''''''''" [no effect] in component "rear left tab 2-2 locknut"
ref_plane "WorkPlane1" through (0, 0, 6.1) normal (0, 0, 1) x (1, 0, 0) in component "rear left public motor reserve"
sketch "New stock profile (101)" plane through (0, 0, 6.1) normal (0, 0, 1) x (1, 0, 0) in component "rear left public motor reserve"
  circle A0 centre (19, -19) radius 19
extrude "New 1''''''''''''''''''''''''''''''''''''''''''''''''''''''''''''''''''''''''''''''''''''''''''''''''''''" add sketch "New stock profile (101)" along normal blind 50.36 separate body makes body 227 in component "rear left public motor reserve"
ref_plane "WorkPlane1" through (0, 0, 68.1) normal (0, 0, 1) x (1, 0, 0) in component "rear left public turning fork"
sketch "New stock profile (102)" plane through (0, 0, 68.1) normal (0, 0, 1) x (1, 0, 0) in component "rear left public turning fork"
  circle A0 centre (-265, 265) radius 19.95
extrude "New 1'''''''''''''''''''''''''''''''''''''''''''''''''''''''''''''''''''''''''''''''''''''''''''''''''''''" add sketch "New stock profile (102)" along normal blind 23 separate body makes body 228 in component "rear left public turning fork"
ref_plane "WorkPlane2" through (0, 0, 68.1) normal (0, 0, 1) x (1, 0, 0) in component "rear left public turning fork"
sketch "Join stock profile (38)" plane through (0, 0, 68.1) normal (0, 0, 1) x (1, 0, 0) in component "rear left public turning fork"
  circle A0 centre (-265, 265) radius 25.5
extrude "Join 2'''''''''''''''''''''''''''''''''''''" add sketch "Join stock profile (38)" along normal blind 5 bodies 228 in component "rear left public turning fork"
ref_plane "WorkPlane3" through (0, 0, 33.1) normal (0, 0, 1) x (1, 0, 0) in component "rear left public turning fork"